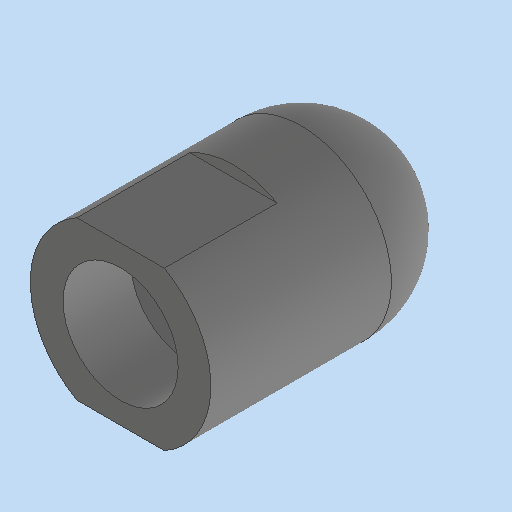
# Autodesk Inventor part: MM0948AN130_G13_103
Saved by Autodesk Inventor 2023.3 (Build 273359000, 359)
## iProperties
Created: 2024-11-11
Part Number: MM0948AN130_G13_103
Material: 1.2099 X5CrS12
Description: =<RBPARTNOTITLE2>
Document SubType Name: Modeling
Designer: RIC7AN
Mass: 3.12579 g
Surface Area: 4.6724 cm^2
Volume: 0.39819 cm^3
Density: 7.85 g/cm^3
Appearance: Stahl - rostfrei AnP
RBPARTMADEOF: Ø8 x 12 (FM)
RBDRAWINGMISSINGSPEC: --
AnP_Kategorie: 1
RBPARTNOTITLE2: Anfertigungsteil
RBSURFACE: --
RBPARTNOTITLE1: manufactured part
RBSURFACE2: --
AnP_Material: =<Material>
RBMATERIAL: =<Material>
RBMATNO: =<Part Number>
RBPARTNO: SIEHE MNR
MaxAbmaße: 8 x 12 x 8 (FM)
Author: RIC7AN
Keywords: =<RBPARTMADEOF>
Comments: =<RBSURFACE2>
Revision Number: 01
Autodesk Inventor part; units mm, degrees
ref_plane "YZ Plane" through (0, 0, 0) normal (1, 0, 0) x (0, 1, 0)
ref_plane "XZ Plane" through (0, 0, 0) normal (0, 1, 0) x (-1, 0, 0)
ref_plane "XY Plane" through (0, 0, 0) normal (0, 0, 1) x (1, 0, 0)
sketch "Skizze1" plane through (0, 0, 0) normal (0, 0, 1) x (1, 0, 0)
  line L0 (-4, 8) -> (0, 8)
  line L1 (0, 8) -> (0, 0)
  line L2 (0, 0) -> (-4, 0)
  line L3 (-4, 0) -> (-4, 8)
  arc A0 (0, 12) -> (-4, 8) centre (0, 8) ccw
  line L4 (0, 12) -> (0, 8)
  dimension "d0" = 8
  dimension "d1" = 4
  constraints: 10 end point, 2 parallel, 2 point on circle, 1 centre point, 1 coincident, 1 horizontal, 1 perpendicular, 1 vertical
  measures "d0" distance of L2.end L0.start
  measures "d1" distance between parallel lines of L1 L3
revolve "Umdrehung1" add sketch "Skizze1" angle 360 about axis through (0, 12, 0) along (0, -1, 0)
sketch "Skizze2" plane through (0, 0, 0) normal (0, -1, 0) x (1, 0, 0)
  point P0 (0, 0)
  point P1 (0, 0)
  constraints: 1 coincident
hole "Bohrung1" at (0, 0, 0) direction (0, 1, 0) diameter 5.1 depth 3 tip angle 118
sketch "Skizze3" plane through (0, 0, 0) normal (0, -1, 0) x (1, 0, 0)
  point P0 (0, 0)
  point P1 (0, 0)
  constraints: 1 coincident
hole "Bohrung2" at (0, 0, 0) direction (0, 1, 0) diameter 3.242 depth 10 tip angle 118 thread size "M4x0.7" designation "M4" class "6H" standard "ISO Metric profile"
sketch "Skizze4" plane through (0, 0, 0) normal (0, -1, 0) x (1, 0, 0)
  circle A0 centre (0, 0) radius 2.55 projected
  circle A1 centre (0, 0) radius 4 projected
  line L0 (-1.9365, 3.5) -> (1.9365, 3.5)
  line L1 (1.9365, 3.5) -> (1.9365, -3.5)
  line L2 (1.9365, -3.5) -> (-1.9365, -3.5)
  line L3 (-1.9365, -3.5) -> (-1.9365, 3.5)
  line L4 (0, 5.6) -> (0, -5.6) projected
  line L5 (-5.6, 0) -> (5.6, 0) projected
  point P0 (0, 0)
  point P1 (-1.9365, -3.5)
  dimension "d17" = 7
  constraints: 8 end point, 2 parallel, 2 point on circle, 1 horizontal, 1 perpendicular, 1 other
  measures "d17" distance of L0.end L1.end
extrude "Extrusion1" cut sketch "Skizze4" against normal blind 5 contours L0 L4 A1 | A1 L4 L2 | L0 A1 L4 | L4 A1 L2
